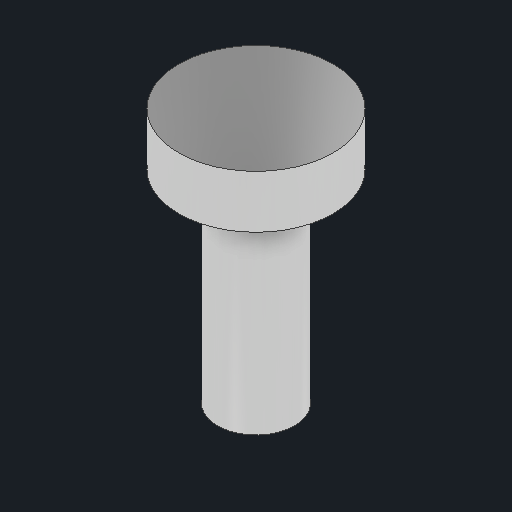
# Autodesk Inventor part: screw_M2x5_selftap_pan
Saved by Autodesk Inventor 2027.1 (Build 311270010, 270A)
## iProperties
Created: 2026-10-29
Part Number: screw_M2x5_selftap_pan
Material: Generic
Document SubType Name: Modeling
Designer: alexg
Density: 1 g/cm^3
Appearance: Chrome - Polished
Author: alexg
Autodesk Inventor part; units mm, degrees
ref_plane "YZ Plane" through (0, 0, 0) normal (1, 0, 0) x (0, 1, 0)
ref_plane "XZ Plane" through (0, 0, 0) normal (0, 1, 0) x (-1, 0, 0)
ref_plane "XY Plane" through (0, 0, 0) normal (0, 0, 1) x (1, 0, 0)
sketch "Head sketch" plane through (0, 0, 0) normal (0, 1, 0) x (-1, 0, 0)
  circle A0 centre (0, 0) radius 1.9
  constraints: 1 centre point
extrude "Head" add sketch "Head sketch" along normal blind 1.3
sketch "Shank sketch" plane through (0, 0, 0) normal (0, 1, 0) x (-1, 0, 0)
  circle A0 centre (0, 0) radius 0.95
  constraints: 1 centre point
extrude "Shank" add sketch "Shank sketch" against normal blind 5
body "Solid1"
